Autodesk Fusion 360 part; units mm, degrees
(part 5 of 28)
  line L2664 (86.6129, 73.4851, -1.4859) -> (86.6129, 65.3433, -1.4859)
  line L2665 (86.6129, 65.3433, -1.4859) -> (86.7412, 65.3016, -1.4859)
  line L2666 (86.7412, 65.3016, -1.4859) -> (86.916, 65.2126, -1.4859)
  line L2667 (86.916, 65.2126, -1.4859) -> (87.0747, 65.0973, -1.4859)
  line L2668 (87.0747, 65.0973, -1.4859) -> (87.2134, 64.9586, -1.4859)
  line L2669 (87.2134, 64.9586, -1.4859) -> (87.3287, 64.7999, -1.4859)
  line L2670 (87.3287, 64.7999, -1.4859) -> (87.4177, 64.6251, -1.4859)
  line L2671 (87.4177, 64.6251, -1.4859) -> (87.4784, 64.4386, -1.4859)
  line L2672 (87.4784, 64.4386, -1.4859) -> (87.509, 64.2448, -1.4859)
  line L2673 (87.509, 64.2448, -1.4859) -> (87.509, 64.0487, -1.4859)
  line L2674 (87.509, 64.0487, -1.4859) -> (87.4784, 63.855, -1.4859)
  line L2675 (87.4784, 63.855, -1.4859) -> (87.4177, 63.6684, -1.4859)
  line L2676 (87.4177, 63.6684, -1.4859) -> (87.3287, 63.4936, -1.4859)
  line L2677 (87.3287, 63.4936, -1.4859) -> (87.2134, 63.335, -1.4859)
  line L2678 (87.2134, 63.335, -1.4859) -> (87.0747, 63.1963, -1.4859)
  line L2679 (87.0747, 63.1963, -1.4859) -> (86.916, 63.081, -1.4859)
  line L2680 (86.916, 63.081, -1.4859) -> (86.7412, 62.9919, -1.4859)
  line L2681 (86.7412, 62.9919, -1.4859) -> (86.5547, 62.9313, -1.4859)
  line L2682 (86.5797, 62.9563) -> (86.5797, 62.9563)
  line L2683 (86.5547, 62.9313, -1.4859) -> (86.5547, 55.068, -1.4859)
  line L2684 (86.5547, 55.068, -1.4859) -> (86.5947, 55.0476, -1.4859)
  line L2685 (86.5947, 55.0476, -1.4859) -> (86.7503, 54.9346, -1.4859)
  line L2686 (86.7503, 54.9346, -1.4859) -> (86.8862, 54.7987, -1.4859)
  line L2687 (86.8862, 54.7987, -1.4859) -> (86.9992, 54.6432, -1.4859)
  line L2688 (86.9992, 54.6432, -1.4859) -> (87.0864, 54.4719, -1.4859)
  line L2689 (87.0864, 54.4719, -1.4859) -> (87.1458, 54.2891, -1.4859)
  line L2690 (87.1458, 54.2891, -1.4859) -> (87.1759, 54.0992, -1.4859)
  line L2691 (87.1759, 54.0992, -1.4859) -> (87.1797, 54.0031, -1.4859)
  line L2692 (87.1797, 54.0031, -1.4859) -> (87.1797, 53.4531, -1.4859)
  line L2693 (87.1797, 53.4531, -1.4859) -> (87.1759, 53.357, -1.4859)
  line L2694 (87.1759, 53.357, -1.4859) -> (87.1458, 53.1671, -1.4859)
  line L2695 (87.1458, 53.1671, -1.4859) -> (87.0864, 52.9843, -1.4859)
  line L2696 (87.0864, 52.9843, -1.4859) -> (86.9992, 52.8131, -1.4859)
  line L2697 (86.9992, 52.8131, -1.4859) -> (86.8862, 52.6575, -1.4859)
  line L2698 (86.8862, 52.6575, -1.4859) -> (86.7503, 52.5216, -1.4859)
  line L2699 (86.7503, 52.5216, -1.4859) -> (86.5947, 52.4086, -1.4859)
  line L2700 (86.5947, 52.4086, -1.4859) -> (86.4235, 52.3214, -1.4859)
  line L2701 (86.4235, 52.3214, -1.4859) -> (86.2407, 52.262, -1.4859)
  line L2702 (86.2407, 52.262, -1.4859) -> (86.0508, 52.2319, -1.4859)
  line L2703 (86.0508, 52.2319, -1.4859) -> (85.8586, 52.2319, -1.4859)
  line L2704 (85.8586, 52.2319, -1.4859) -> (85.6687, 52.262, -1.4859)
  line L2705 (85.6687, 52.262, -1.4859) -> (85.4859, 52.3214, -1.4859)
  line L2706 (85.4859, 52.3214, -1.4859) -> (85.3146, 52.4086, -1.4859)
  line L2707 (85.3146, 52.4086, -1.4859) -> (85.1591, 52.5216, -1.4859)
  line L2708 (85.1591, 52.5216, -1.4859) -> (85.0232, 52.6575, -1.4859)
  line L2709 (85.0232, 52.6575, -1.4859) -> (84.9102, 52.8131, -1.4859)
  line L2710 (84.9102, 52.8131, -1.4859) -> (84.8229, 52.9843, -1.4859)
  line L2711 (84.8229, 52.9843, -1.4859) -> (84.7635, 53.1671, -1.4859)
  line L2712 (84.7635, 53.1671, -1.4859) -> (84.7335, 53.357, -1.4859)
  line L2713 (84.7335, 53.357, -1.4859) -> (84.7297, 53.4531, -1.4859)
  line L2714 (84.7297, 53.4531, -1.4859) -> (84.7297, 54.0031, -1.4859)
  line L2715 (84.7297, 54.0031, -1.4859) -> (84.7335, 54.0992, -1.4859)
  line L2716 (84.7335, 54.0992, -1.4859) -> (84.7635, 54.2891, -1.4859)
  line L2717 (84.7635, 54.2891, -1.4859) -> (84.8229, 54.4719, -1.4859)
  line L2718 (84.8229, 54.4719, -1.4859) -> (84.9102, 54.6432, -1.4859)
  line L2719 (84.9102, 54.6432, -1.4859) -> (85.0232, 54.7987, -1.4859)
  line L2720 (85.0232, 54.7987, -1.4859) -> (85.1591, 54.9346, -1.4859)
  line L2721 (85.1591, 54.9346, -1.4859) -> (85.3146, 55.0476, -1.4859)
  line L2722 (85.3146, 55.0476, -1.4859) -> (85.3547, 55.068, -1.4859)
  line L2723 (85.3547, 55.068, -1.4859) -> (85.3547, 62.9691, -1.4859)
  line L2724 (85.3547, 62.9691, -1.4859) -> (85.2845, 62.9919, -1.4859)
  line L2725 (85.2845, 62.9919, -1.4859) -> (85.1098, 63.081, -1.4859)
  line L2726 (85.1098, 63.081, -1.4859) -> (84.9511, 63.1963, -1.4859)
  line L2727 (84.9511, 63.1963, -1.4859) -> (84.8124, 63.335, -1.4859)
  line L2728 (84.8124, 63.335, -1.4859) -> (84.6971, 63.4936, -1.4859)
  line L2729 (84.6971, 63.4936, -1.4859) -> (84.608, 63.6684, -1.4859)
  line L2730 (84.608, 63.6684, -1.4859) -> (84.5474, 63.855, -1.4859)
  line L2731 (84.5474, 63.855, -1.4859) -> (84.5167, 64.0487, -1.4859)
  line L2732 (84.5167, 64.0487, -1.4859) -> (84.5167, 64.2448, -1.4859)
  line L2733 (84.5167, 64.2448, -1.4859) -> (84.5474, 64.4386, -1.4859)
  line L2734 (84.5474, 64.4386, -1.4859) -> (84.608, 64.6251, -1.4859)
  line L2735 (84.608, 64.6251, -1.4859) -> (84.6971, 64.7999, -1.4859)
  line L2736 (84.6971, 64.7999, -1.4859) -> (84.8124, 64.9586, -1.4859)
  line L2737 (84.8124, 64.9586, -1.4859) -> (84.9511, 65.0973, -1.4859)
  line L2738 (84.9511, 65.0973, -1.4859) -> (85.1098, 65.2126, -1.4859)
  line L2739 (85.1098, 65.2126, -1.4859) -> (85.2845, 65.3016, -1.4859)
  line L2740 (85.2845, 65.3016, -1.4859) -> (85.4129, 65.3433, -1.4859)
  line L2741 (85.4129, 65.3433, -1.4859) -> (85.4129, 73.4699, -1.4859)
  line L2742 (85.4129, 73.4699, -1.4859) -> (85.3671, 73.5005, -1.4859)
  line L2743 (85.3671, 73.5005, -1.4859) -> (85.2285, 73.6391, -1.4859)
  line L2744 (85.2285, 73.6391, -1.4859) -> (85.1196, 73.8021, -1.4859)
  line L2745 (85.1196, 73.8021, -1.4859) -> (85.0446, 73.9832, -1.4859)
  line L2746 (85.0446, 73.9832, -1.4859) -> (85.0063, 74.1755, -1.4859)
  line L2747 (85.0063, 74.1755, -1.4859) -> (85.0015, 74.2735, -1.4859)
  line L2748 (85.0015, 74.2735, -1.4859) -> (85.0015, 75.4735, -1.4859)
  line L2749 (85.0015, 75.4735, -1.4859) -> (85.0063, 75.5715, -1.4859)
  line L2750 (85.0063, 75.5715, -1.4859) -> (85.0446, 75.7638, -1.4859)
  line L2751 (85.0446, 75.7638, -1.4859) -> (85.1196, 75.9449, -1.4859)
  line L2752 (85.1196, 75.9449, -1.4859) -> (85.2285, 76.1079, -1.4859)
  line L2753 (85.2285, 76.1079, -1.4859) -> (85.3671, 76.2465, -1.4859)
  line L2754 (85.3671, 76.2465, -1.4859) -> (85.5301, 76.3554, -1.4859)
  line L2755 (85.5301, 76.3554, -1.4859) -> (85.7112, 76.4304, -1.4859)
  line L2756 (85.7112, 76.4304, -1.4859) -> (85.9035, 76.4687, -1.4859)
  line L2757 (85.9035, 76.4687, -1.4859) -> (86.0995, 76.4687, -1.4859)
  line L2758 (86.0995, 76.4687, -1.4859) -> (86.2918, 76.4304, -1.4859)
  line L2759 (121.2168, 76.4304, -1.4859) -> (121.3979, 76.3554, -1.4859)
  line L2760 (121.3979, 76.3554, -1.4859) -> (121.5609, 76.2465, -1.4859)
  line L2761 (121.5609, 76.2465, -1.4859) -> (121.6995, 76.1079, -1.4859)
  line L2762 (121.6995, 76.1079, -1.4859) -> (121.8084, 75.9449, -1.4859)
  line L2763 (121.8084, 75.9449, -1.4859) -> (121.8835, 75.7638, -1.4859)
  line L2764 (121.8835, 75.7638, -1.4859) -> (121.9217, 75.5715, -1.4859)
  line L2765 (121.9217, 75.5715, -1.4859) -> (121.9265, 75.4735, -1.4859)
  line L2766 (121.9265, 75.4735, -1.4859) -> (121.9265, 74.2735, -1.4859)
  line L2767 (121.9265, 74.2735, -1.4859) -> (121.9217, 74.1755, -1.4859)
  line L2768 (121.9217, 74.1755, -1.4859) -> (121.8835, 73.9832, -1.4859)
  line L2769 (121.8835, 73.9832, -1.4859) -> (121.8084, 73.8021, -1.4859)
  line L2770 (121.8084, 73.8021, -1.4859) -> (121.6995, 73.6391, -1.4859)
  line L2771 (121.6995, 73.6391, -1.4859) -> (121.5609, 73.5005, -1.4859)
  line L2772 (121.5609, 73.5005, -1.4859) -> (121.5379, 73.4851, -1.4859)
  line L2773 (121.5379, 73.4851, -1.4859) -> (121.5379, 65.3433, -1.4859)
  line L2774 (121.5379, 65.3433, -1.4859) -> (121.6662, 65.3016, -1.4859)
  line L2775 (121.6662, 65.3016, -1.4859) -> (121.841, 65.2126, -1.4859)
  line L2776 (121.841, 65.2126, -1.4859) -> (121.9997, 65.0973, -1.4859)
  line L2777 (121.9997, 65.0973, -1.4859) -> (122.1384, 64.9586, -1.4859)
  line L2778 (122.1384, 64.9586, -1.4859) -> (122.2537, 64.7999, -1.4859)
  line L2779 (122.2537, 64.7999, -1.4859) -> (122.3427, 64.6251, -1.4859)
  line L2780 (122.3427, 64.6251, -1.4859) -> (122.4033, 64.4386, -1.4859)
  line L2781 (122.4033, 64.4386, -1.4859) -> (122.434, 64.2448, -1.4859)
  line L2782 (122.434, 64.2448, -1.4859) -> (122.434, 64.0487, -1.4859)
  line L2783 (122.434, 64.0487, -1.4859) -> (122.4033, 63.855, -1.4859)
  line L2784 (122.4034, 63.855, -1.4859) -> (122.3427, 63.6684, -1.4859)
  line L2785 (122.3427, 63.6684, -1.4859) -> (122.2537, 63.4936, -1.4859)
  line L2786 (122.2537, 63.4936, -1.4859) -> (122.1384, 63.335, -1.4859)
  line L2787 (122.1384, 63.335, -1.4859) -> (121.9997, 63.1963, -1.4859)
  line L2788 (121.9997, 63.1963, -1.4859) -> (121.841, 63.081, -1.4859)
  line L2789 (121.841, 63.081, -1.4859) -> (121.6662, 62.9919, -1.4859)
  line L2790 (121.6662, 62.9919, -1.4859) -> (121.4797, 62.9313, -1.4859)
  line L2791 (121.5047, 62.9563) -> (121.5047, 62.9563)
  line L2792 (121.4797, 62.9313, -1.4859) -> (121.4797, 55.068, -1.4859)
  line L2793 (121.4797, 55.068, -1.4859) -> (121.5197, 55.0476, -1.4859)
  line L2794 (121.5197, 55.0476, -1.4859) -> (121.6753, 54.9346, -1.4859)
  line L2795 (121.6753, 54.9346, -1.4859) -> (121.8112, 54.7987, -1.4859)
  line L2796 (121.8112, 54.7987, -1.4859) -> (121.9242, 54.6432, -1.4859)
  line L2797 (121.9242, 54.6432, -1.4859) -> (122.0114, 54.4719, -1.4859)
  line L2798 (122.0114, 54.4719, -1.4859) -> (122.0708, 54.2891, -1.4859)
  line L2799 (122.0708, 54.2891, -1.4859) -> (122.1009, 54.0992, -1.4859)
  line L2800 (122.1009, 54.0992, -1.4859) -> (122.1047, 54.0031, -1.4859)
  line L2801 (122.1047, 54.0031, -1.4859) -> (122.1047, 53.4531, -1.4859)
  line L2802 (122.1047, 53.4531, -1.4859) -> (122.1009, 53.357, -1.4859)
  line L2803 (122.1009, 53.357, -1.4859) -> (122.0708, 53.1671, -1.4859)
  line L2804 (122.0708, 53.1671, -1.4859) -> (122.0114, 52.9843, -1.4859)
  line L2805 (122.0114, 52.9843, -1.4859) -> (121.9242, 52.8131, -1.4859)
  line L2806 (121.9242, 52.8131, -1.4859) -> (121.8112, 52.6575, -1.4859)
  line L2807 (121.8112, 52.6575, -1.4859) -> (121.6753, 52.5216, -1.4859)
  line L2808 (121.6753, 52.5216, -1.4859) -> (121.5197, 52.4086, -1.4859)
  line L2809 (121.5197, 52.4086, -1.4859) -> (121.3485, 52.3214, -1.4859)
  line L2810 (121.3485, 52.3214, -1.4859) -> (121.1657, 52.262, -1.4859)
  line L2811 (121.1657, 52.262, -1.4859) -> (120.9758, 52.2319, -1.4859)
  line L2812 (120.9758, 52.2319, -1.4859) -> (120.7836, 52.2319, -1.4859)
  line L2813 (120.7836, 52.2319, -1.4859) -> (120.5937, 52.262, -1.4859)
  line L2814 (120.5937, 52.262, -1.4859) -> (120.4109, 52.3214, -1.4859)
  line L2815 (120.4109, 52.3214, -1.4859) -> (120.2396, 52.4086, -1.4859)
  line L2816 (120.2396, 52.4086, -1.4859) -> (120.0841, 52.5216, -1.4859)
  line L2817 (120.0841, 52.5216, -1.4859) -> (119.9482, 52.6575, -1.4859)
  line L2818 (119.9482, 52.6575, -1.4859) -> (119.8352, 52.8131, -1.4859)
  line L2819 (119.8352, 52.8131, -1.4859) -> (119.7479, 52.9843, -1.4859)
  line L2820 (119.7479, 52.9843, -1.4859) -> (119.6885, 53.1671, -1.4859)
  line L2821 (119.6885, 53.1671, -1.4859) -> (119.6585, 53.357, -1.4859)
  line L2822 (119.6585, 53.357, -1.4859) -> (119.6547, 53.4531, -1.4859)
  line L2823 (119.6547, 53.4531, -1.4859) -> (119.6547, 54.0031, -1.4859)
  line L2824 (119.6547, 54.0031, -1.4859) -> (119.6585, 54.0992, -1.4859)
  line L2825 (119.6585, 54.0992, -1.4859) -> (119.6885, 54.2891, -1.4859)
  line L2826 (119.6885, 54.2891, -1.4859) -> (119.7479, 54.4719, -1.4859)
  line L2827 (119.7479, 54.4719, -1.4859) -> (119.8352, 54.6432, -1.4859)
  line L2828 (119.8352, 54.6432, -1.4859) -> (119.9482, 54.7987, -1.4859)
  line L2829 (119.9482, 54.7987, -1.4859) -> (120.0841, 54.9346, -1.4859)
  line L2830 (120.0841, 54.9346, -1.4859) -> (120.2396, 55.0476, -1.4859)
  line L2831 (120.2396, 55.0476, -1.4859) -> (120.2797, 55.068, -1.4859)
  line L2832 (120.2797, 55.068, -1.4859) -> (120.2797, 62.9691, -1.4859)
  line L2833 (120.2797, 62.9691, -1.4859) -> (120.2095, 62.9919, -1.4859)
  line L2834 (120.2095, 62.9919, -1.4859) -> (120.0348, 63.081, -1.4859)
  line L2835 (120.0348, 63.081, -1.4859) -> (119.8761, 63.1963, -1.4859)
  line L2836 (119.8761, 63.1963, -1.4859) -> (119.7374, 63.335, -1.4859)
  line L2837 (119.7374, 63.335, -1.4859) -> (119.6221, 63.4936, -1.4859)
  line L2838 (119.6221, 63.4936, -1.4859) -> (119.533, 63.6684, -1.4859)
  line L2839 (119.533, 63.6684, -1.4859) -> (119.4724, 63.855, -1.4859)
  line L2840 (119.4724, 63.855, -1.4859) -> (119.4417, 64.0487, -1.4859)
  line L2841 (119.4417, 64.0487, -1.4859) -> (119.4417, 64.2448, -1.4859)
  line L2842 (119.4417, 64.2448, -1.4859) -> (119.4724, 64.4386, -1.4859)
  line L2843 (119.4724, 64.4386, -1.4859) -> (119.533, 64.6251, -1.4859)
  line L2844 (119.533, 64.6251, -1.4859) -> (119.6221, 64.7999, -1.4859)
  line L2845 (119.6221, 64.7999, -1.4859) -> (119.7374, 64.9586, -1.4859)
  line L2846 (119.7374, 64.9586, -1.4859) -> (119.8761, 65.0973, -1.4859)
  line L2847 (119.8761, 65.0973, -1.4859) -> (120.0348, 65.2126, -1.4859)
  line L2848 (120.0348, 65.2126, -1.4859) -> (120.2095, 65.3016, -1.4859)
  line L2849 (120.2095, 65.3016, -1.4859) -> (120.3379, 65.3433, -1.4859)
  line L2850 (120.3379, 65.3433, -1.4859) -> (120.3379, 73.4699, -1.4859)
  line L2851 (120.3379, 73.4699, -1.4859) -> (120.2921, 73.5005, -1.4859)
  line L2852 (120.2921, 73.5005, -1.4859) -> (120.1535, 73.6391, -1.4859)
  line L2853 (120.1535, 73.6391, -1.4859) -> (120.0446, 73.8021, -1.4859)
  line L2854 (120.0446, 73.8021, -1.4859) -> (119.9696, 73.9832, -1.4859)
  line L2855 (119.9696, 73.9832, -1.4859) -> (119.9313, 74.1755, -1.4859)
  line L2856 (119.9313, 74.1755, -1.4859) -> (119.9265, 74.2735, -1.4859)
  line L2857 (119.9265, 74.2735, -1.4859) -> (119.9265, 75.4735, -1.4859)
  line L2858 (119.9265, 75.4735, -1.4859) -> (119.9313, 75.5715, -1.4859)
  line L2859 (119.9313, 75.5715, -1.4859) -> (119.9696, 75.7638, -1.4859)
  line L2860 (119.9696, 75.7638, -1.4859) -> (120.0446, 75.9449, -1.4859)
  line L2861 (120.0446, 75.9449, -1.4859) -> (120.1535, 76.1079, -1.4859)
  line L2862 (120.1535, 76.1079, -1.4859) -> (120.2921, 76.2465, -1.4859)
  line L2863 (120.2921, 76.2465, -1.4859) -> (120.4551, 76.3554, -1.4859)
  line L2864 (120.4551, 76.3554, -1.4859) -> (120.6362, 76.4304, -1.4859)
  line L2865 (120.6362, 76.4304, -1.4859) -> (120.8285, 76.4687, -1.4859)
  line L2866 (120.8285, 76.4687, -1.4859) -> (121.0245, 76.4687, -1.4859)
  line L2867 (121.0245, 76.4687, -1.4859) -> (121.2168, 76.4304, -1.4859)
  line L2868 (32.9849, 62.5322, -1.4859) -> (33.1714, 62.4716, -1.4859)
  line L2869 (33.1714, 62.4716, -1.4859) -> (33.3462, 62.3825, -1.4859)
  line L2870 (33.3462, 62.3825, -1.4859) -> (33.5049, 62.2672, -1.4859)
  line L2871 (33.5049, 62.2672, -1.4859) -> (33.6436, 62.1286, -1.4859)
  line L2872 (33.6436, 62.1286, -1.4859) -> (33.7588, 61.9699, -1.4859)
  line L2873 (33.7588, 61.9699, -1.4859) -> (33.8479, 61.7951, -1.4859)
  line L2874 (33.8479, 61.7951, -1.4859) -> (33.9085, 61.6085, -1.4859)
  line L2875 (33.9085, 61.6085, -1.4859) -> (33.9392, 61.4148, -1.4859)
  line L2876 (33.9392, 61.4148, -1.4859) -> (33.943, 61.3167, -1.4859)
  line L2877 (33.943, 61.3167, -1.4859) -> (33.943, 60.8167, -1.4859)
  line L2878 (33.943, 60.8167, -1.4859) -> (33.9392, 60.7187, -1.4859)
  line L2879 (33.9392, 60.7187, -1.4859) -> (33.9085, 60.5249, -1.4859)
  line L2880 (33.9085, 60.5249, -1.4859) -> (33.8479, 60.3384, -1.4859)
  line L2881 (33.8479, 60.3384, -1.4859) -> (33.7588, 60.1636, -1.4859)
  line L2882 (33.7588, 60.1636, -1.4859) -> (33.6436, 60.0049, -1.4859)
  line L2883 (33.6436, 60.0049, -1.4859) -> (33.5049, 59.8662, -1.4859)
  line L2884 (33.5049, 59.8662, -1.4859) -> (33.3462, 59.7509, -1.4859)
  line L2885 (33.3462, 59.7509, -1.4859) -> (33.1714, 59.6619, -1.4859)
  line L2886 (33.1714, 59.6619, -1.4859) -> (32.9848, 59.6013, -1.4859)
  line L2887 (32.9848, 59.6013, -1.4859) -> (32.7911, 59.5706, -1.4859)
  line L2888 (32.7911, 59.5706, -1.4859) -> (32.595, 59.5706, -1.4859)
  line L2889 (32.595, 59.5706, -1.4859) -> (32.4012, 59.6013, -1.4859)
  line L2890 (32.4012, 59.6013, -1.4859) -> (32.2147, 59.6619, -1.4859)
  line L2891 (32.2147, 59.6619, -1.4859) -> (32.0399, 59.7509, -1.4859)
  line L2892 (32.0399, 59.7509, -1.4859) -> (31.8812, 59.8662, -1.4859)
  line L2893 (31.8812, 59.8662, -1.4859) -> (31.7425, 60.0049, -1.4859)
  line L2894 (31.7425, 60.0049, -1.4859) -> (31.6272, 60.1636, -1.4859)
  line L2895 (31.6272, 60.1636, -1.4859) -> (31.5382, 60.3384, -1.4859)
  line L2896 (31.5382, 60.3384, -1.4859) -> (31.4776, 60.5249, -1.4859)
  line L2897 (31.4776, 60.5249, -1.4859) -> (31.4469, 60.7187, -1.4859)
  line L2898 (31.4469, 60.7187, -1.4859) -> (31.443, 60.8167, -1.4859)
  line L2899 (31.443, 60.8167, -1.4859) -> (31.443, 61.3167, -1.4859)
  line L2900 (31.443, 61.3167, -1.4859) -> (31.4469, 61.4148, -1.4859)
  line L2901 (31.4469, 61.4148, -1.4859) -> (31.4776, 61.6085, -1.4859)
  line L2902 (31.4776, 61.6085, -1.4859) -> (31.5382, 61.7951, -1.4859)
  line L2903 (31.5382, 61.7951, -1.4859) -> (31.6272, 61.9699, -1.4859)
  line L2904 (31.6272, 61.9699, -1.4859) -> (31.7425, 62.1286, -1.4859)
  line L2905 (31.7425, 62.1286, -1.4859) -> (31.8812, 62.2672, -1.4859)
  line L2906 (31.8812, 62.2672, -1.4859) -> (32.0399, 62.3825, -1.4859)
  line L2907 (32.0399, 62.3825, -1.4859) -> (32.2147, 62.4716, -1.4859)
  line L2908 (32.2147, 62.4716, -1.4859) -> (32.4012, 62.5322, -1.4859)
  line L2909 (32.4012, 62.5322, -1.4859) -> (32.595, 62.5629, -1.4859)
  line L2910 (32.595, 62.5629, -1.4859) -> (32.7911, 62.5629, -1.4859)
  line L2911 (32.7911, 62.5629, -1.4859) -> (32.9848, 62.5322, -1.4859)
  line L2912 (67.9098, 62.5322, -1.4859) -> (68.0964, 62.4716, -1.4859)
  line L2913 (68.0964, 62.4716, -1.4859) -> (68.2712, 62.3825, -1.4859)
  line L2914 (68.2712, 62.3825, -1.4859) -> (68.4299, 62.2672, -1.4859)
  line L2915 (68.4299, 62.2672, -1.4859) -> (68.5686, 62.1286, -1.4859)
  line L2916 (68.5685, 62.1286, -1.4859) -> (68.6838, 61.9699, -1.4859)
  line L2917 (68.6838, 61.9699, -1.4859) -> (68.7729, 61.7951, -1.4859)
  line L2918 (68.7729, 61.7951, -1.4859) -> (68.8335, 61.6085, -1.4859)
  line L2919 (68.8335, 61.6085, -1.4859) -> (68.8642, 61.4148, -1.4859)
  line L2920 (68.8642, 61.4148, -1.4859) -> (68.868, 61.3167, -1.4859)
  line L2921 (68.868, 61.3167, -1.4859) -> (68.868, 60.8167, -1.4859)
  line L2922 (68.868, 60.8167, -1.4859) -> (68.8642, 60.7187, -1.4859)
  line L2923 (68.8642, 60.7187, -1.4859) -> (68.8335, 60.5249, -1.4859)
  line L2924 (68.8335, 60.5249, -1.4859) -> (68.7729, 60.3384, -1.4859)
  line L2925 (68.7729, 60.3384, -1.4859) -> (68.6838, 60.1636, -1.4859)
  line L2926 (68.6838, 60.1636, -1.4859) -> (68.5686, 60.0049, -1.4859)
  line L2927 (68.5685, 60.0049, -1.4859) -> (68.4299, 59.8662, -1.4859)
  line L2928 (68.4299, 59.8662, -1.4859) -> (68.2712, 59.7509, -1.4859)
  line L2929 (68.2712, 59.7509, -1.4859) -> (68.0964, 59.6619, -1.4859)
  line L2930 (68.0964, 59.6619, -1.4859) -> (67.9099, 59.6013, -1.4859)
  line L2931 (67.9098, 59.6013, -1.4859) -> (67.7161, 59.5706, -1.4859)
  line L2932 (67.7161, 59.5706, -1.4859) -> (67.52, 59.5706, -1.4859)
  line L2933 (67.52, 59.5706, -1.4859) -> (67.3262, 59.6013, -1.4859)
  line L2934 (67.3262, 59.6013, -1.4859) -> (67.1397, 59.6619, -1.4859)
  line L2935 (67.1397, 59.6619, -1.4859) -> (66.9649, 59.7509, -1.4859)
  line L2936 (66.9649, 59.7509, -1.4859) -> (66.8062, 59.8662, -1.4859)
  line L2937 (66.8062, 59.8662, -1.4859) -> (66.6675, 60.0049, -1.4859)
  line L2938 (66.6675, 60.0049, -1.4859) -> (66.5522, 60.1636, -1.4859)
  line L2939 (66.5522, 60.1636, -1.4859) -> (66.4632, 60.3384, -1.4859)
  line L2940 (66.4632, 60.3384, -1.4859) -> (66.4026, 60.5249, -1.4859)
  line L2941 (66.4026, 60.5249, -1.4859) -> (66.3719, 60.7187, -1.4859)
  line L2942 (66.3719, 60.7187, -1.4859) -> (66.368, 60.8167, -1.4859)
  line L2943 (66.368, 60.8167, -1.4859) -> (66.368, 61.3167, -1.4859)
  line L2944 (66.368, 61.3167, -1.4859) -> (66.3719, 61.4148, -1.4859)
  line L2945 (66.3719, 61.4148, -1.4859) -> (66.4026, 61.6085, -1.4859)
  line L2946 (66.4026, 61.6085, -1.4859) -> (66.4632, 61.7951, -1.4859)
  line L2947 (66.4632, 61.7951, -1.4859) -> (66.5522, 61.9699, -1.4859)
  line L2948 (66.5522, 61.9699, -1.4859) -> (66.6675, 62.1286, -1.4859)
  line L2949 (66.6675, 62.1286, -1.4859) -> (66.8062, 62.2672, -1.4859)
  line L2950 (66.8062, 62.2672, -1.4859) -> (66.9649, 62.3825, -1.4859)
  line L2951 (66.9649, 62.3825, -1.4859) -> (67.1397, 62.4716, -1.4859)
  line L2952 (67.1397, 62.4716, -1.4859) -> (67.3262, 62.5322, -1.4859)
  line L2953 (67.3262, 62.5322, -1.4859) -> (67.52, 62.5629, -1.4859)
  line L2954 (67.52, 62.5629, -1.4859) -> (67.7161, 62.5629, -1.4859)
  line L2955 (67.7161, 62.5629, -1.4859) -> (67.9098, 62.5322, -1.4859)
  line L2956 (102.8349, 62.5322, -1.4859) -> (103.0214, 62.4716, -1.4859)
  line L2957 (103.0214, 62.4716, -1.4859) -> (103.1962, 62.3825, -1.4859)
  line L2958 (103.1962, 62.3825, -1.4859) -> (103.3549, 62.2672, -1.4859)
  line L2959 (103.3549, 62.2672, -1.4859) -> (103.4936, 62.1286, -1.4859)
  line L2960 (103.4936, 62.1286, -1.4859) -> (103.6088, 61.9699, -1.4859)
  line L2961 (103.6088, 61.9699, -1.4859) -> (103.6979, 61.7951, -1.4859)
  line L2962 (103.6979, 61.7951, -1.4859) -> (103.7585, 61.6085, -1.4859)
  line L2963 (103.7585, 61.6085, -1.4859) -> (103.7892, 61.4148, -1.4859)
  line L2964 (103.7892, 61.4148, -1.4859) -> (103.793, 61.3167, -1.4859)
  line L2965 (103.793, 61.3167, -1.4859) -> (103.793, 60.8167, -1.4859)
  line L2966 (103.793, 60.8167, -1.4859) -> (103.7892, 60.7187, -1.4859)
  line L2967 (103.7892, 60.7187, -1.4859) -> (103.7585, 60.5249, -1.4859)
  line L2968 (103.7585, 60.5249, -1.4859) -> (103.6979, 60.3384, -1.4859)
  line L2969 (103.6979, 60.3384, -1.4859) -> (103.6088, 60.1636, -1.4859)
  line L2970 (103.6088, 60.1636, -1.4859) -> (103.4936, 60.0049, -1.4859)
  line L2971 (103.4936, 60.0049, -1.4859) -> (103.3549, 59.8662, -1.4859)
  line L2972 (103.3549, 59.8662, -1.4859) -> (103.1962, 59.7509, -1.4859)
  line L2973 (103.1962, 59.7509, -1.4859) -> (103.0214, 59.6619, -1.4859)
  line L2974 (103.0214, 59.6619, -1.4859) -> (102.8349, 59.6013, -1.4859)
  line L2975 (102.8349, 59.6013, -1.4859) -> (102.6411, 59.5706, -1.4859)
  line L2976 (102.6411, 59.5706, -1.4859) -> (102.445, 59.5706, -1.4859)
  line L2977 (102.445, 59.5706, -1.4859) -> (102.2512, 59.6013, -1.4859)
  line L2978 (102.2512, 59.6013, -1.4859) -> (102.0647, 59.6619, -1.4859)
  line L2979 (102.0647, 59.6619, -1.4859) -> (101.8899, 59.7509, -1.4859)
  line L2980 (101.8899, 59.7509, -1.4859) -> (101.7312, 59.8662, -1.4859)
  line L2981 (101.7312, 59.8662, -1.4859) -> (101.5925, 60.0049, -1.4859)
  line L2982 (101.5925, 60.0049, -1.4859) -> (101.4772, 60.1636, -1.4859)
  line L2983 (101.4772, 60.1636, -1.4859) -> (101.3882, 60.3384, -1.4859)
  line L2984 (101.3882, 60.3384, -1.4859) -> (101.3276, 60.5249, -1.4859)
  line L2985 (101.3276, 60.5249, -1.4859) -> (101.2969, 60.7187, -1.4859)
  line L2986 (101.2969, 60.7187, -1.4859) -> (101.293, 60.8167, -1.4859)
  line L2987 (101.293, 60.8167, -1.4859) -> (101.293, 61.3167, -1.4859)
  line L2988 (101.293, 61.3167, -1.4859) -> (101.2969, 61.4148, -1.4859)
  line L2989 (101.2969, 61.4148, -1.4859) -> (101.3276, 61.6085, -1.4859)
  line L2990 (101.3276, 61.6085, -1.4859) -> (101.3882, 61.7951, -1.4859)
  line L2991 (101.3882, 61.7951, -1.4859) -> (101.4772, 61.9699, -1.4859)
  line L2992 (101.4772, 61.9699, -1.4859) -> (101.5925, 62.1286, -1.4859)
  line L2993 (101.5925, 62.1286, -1.4859) -> (101.7312, 62.2672, -1.4859)
  line L2994 (101.7312, 62.2672, -1.4859) -> (101.8899, 62.3825, -1.4859)
  line L2995 (101.8899, 62.3825, -1.4859) -> (102.0647, 62.4716, -1.4859)
  line L2996 (102.0647, 62.4716, -1.4859) -> (102.2512, 62.5322, -1.4859)
  line L2997 (102.2512, 62.5322, -1.4859) -> (102.445, 62.5629, -1.4859)
  line L2998 (102.445, 62.5629, -1.4859) -> (102.6411, 62.5629, -1.4859)
  line L2999 (102.6411, 62.5629, -1.4859) -> (102.8349, 62.5322, -1.4859)
  line L3000 (137.7599, 62.5322, -1.4859) -> (137.9464, 62.4716, -1.4859)
  line L3001 (137.9464, 62.4716, -1.4859) -> (138.1212, 62.3825, -1.4859)
  line L3002 (138.1212, 62.3825, -1.4859) -> (138.2799, 62.2672, -1.4859)
  line L3003 (138.2799, 62.2672, -1.4859) -> (138.4186, 62.1286, -1.4859)
  line L3004 (138.4186, 62.1286, -1.4859) -> (138.5338, 61.9699, -1.4859)
  line L3005 (138.5338, 61.9699, -1.4859) -> (138.6229, 61.7951, -1.4859)
  line L3006 (138.6229, 61.7951, -1.4859) -> (138.6835, 61.6085, -1.4859)
  line L3007 (138.6835, 61.6085, -1.4859) -> (138.7142, 61.4148, -1.4859)
  line L3008 (138.7142, 61.4148, -1.4859) -> (138.718, 61.3167, -1.4859)
  line L3009 (138.718, 61.3167, -1.4859) -> (138.718, 60.8167, -1.4859)
  line L3010 (138.718, 60.8167, -1.4859) -> (138.7142, 60.7187, -1.4859)
  line L3011 (138.7142, 60.7187, -1.4859) -> (138.6835, 60.5249, -1.4859)
  line L3012 (138.6835, 60.5249, -1.4859) -> (138.6229, 60.3384, -1.4859)
  line L3013 (138.6229, 60.3384, -1.4859) -> (138.5338, 60.1636, -1.4859)
  line L3014 (138.5338, 60.1636, -1.4859) -> (138.4186, 60.0049, -1.4859)
  line L3015 (138.4186, 60.0049, -1.4859) -> (138.2799, 59.8662, -1.4859)
  line L3016 (138.2799, 59.8662, -1.4859) -> (138.1212, 59.7509, -1.4859)
  line L3017 (138.1212, 59.7509, -1.4859) -> (137.9464, 59.6619, -1.4859)
  line L3018 (137.9464, 59.6619, -1.4859) -> (137.7599, 59.6013, -1.4859)
  line L3019 (137.7599, 59.6013, -1.4859) -> (137.5661, 59.5706, -1.4859)
  line L3020 (137.5661, 59.5706, -1.4859) -> (137.37, 59.5706, -1.4859)
  line L3021 (137.37, 59.5706, -1.4859) -> (137.1762, 59.6013, -1.4859)
  line L3022 (137.1762, 59.6013, -1.4859) -> (136.9897, 59.6619, -1.4859)
  line L3023 (136.9897, 59.6619, -1.4859) -> (136.8149, 59.7509, -1.4859)
  line L3024 (136.8149, 59.7509, -1.4859) -> (136.6562, 59.8662, -1.4859)
  line L3025 (136.6562, 59.8662, -1.4859) -> (136.5175, 60.0049, -1.4859)
  line L3026 (136.5175, 60.0049, -1.4859) -> (136.4022, 60.1636, -1.4859)
  line L3027 (136.4022, 60.1636, -1.4859) -> (136.3132, 60.3384, -1.4859)
  line L3028 (136.3132, 60.3384, -1.4859) -> (136.2526, 60.5249, -1.4859)
  line L3029 (136.2526, 60.5249, -1.4859) -> (136.2219, 60.7187, -1.4859)
  line L3030 (136.2219, 60.7187, -1.4859) -> (136.218, 60.8167, -1.4859)
  line L3031 (136.218, 60.8167, -1.4859) -> (136.218, 61.3167, -1.4859)
  line L3032 (136.218, 61.3167, -1.4859) -> (136.2219, 61.4148, -1.4859)
  line L3033 (136.2219, 61.4148, -1.4859) -> (136.2526, 61.6085, -1.4859)
  line L3034 (136.2526, 61.6085, -1.4859) -> (136.3132, 61.7951, -1.4859)
  line L3035 (136.3132, 61.7951, -1.4859) -> (136.4022, 61.9699, -1.4859)
  line L3036 (136.4022, 61.9699, -1.4859) -> (136.5175, 62.1286, -1.4859)
  line L3037 (136.5175, 62.1286, -1.4859) -> (136.6562, 62.2672, -1.4859)
  line L3038 (136.6562, 62.2672, -1.4859) -> (136.8149, 62.3825, -1.4859)
  line L3039 (136.8149, 62.3825, -1.4859) -> (136.9897, 62.4716, -1.4859)
  line L3040 (136.9897, 62.4716, -1.4859) -> (137.1762, 62.5322, -1.4859)
  line L3041 (137.1762, 62.5322, -1.4859) -> (137.37, 62.5629, -1.4859)
  line L3042 (137.37, 62.5629, -1.4859) -> (137.5661, 62.5629, -1.4859)
  line L3043 (137.5661, 62.5629, -1.4859) -> (137.7599, 62.5322, -1.4859)
  line L3044 (24.9166, 73.2153, -1.4859) -> (22.9166, 73.2153, -1.4859)
  line L3045 (22.9166, 73.2153, -1.4859) -> (22.9166, 76.4153, -1.4859)
  line L3046 (22.9166, 76.4153, -1.4859) -> (24.9166, 76.4153, -1.4859)
  line L3047 (24.9166, 76.4153, -1.4859) -> (24.9166, 73.2153, -1.4859)
  line L3048 (59.8416, 73.2153, -1.4859) -> (57.8416, 73.2153, -1.4859)
  line L3049 (57.8416, 73.2153, -1.4859) -> (57.8416, 76.4153, -1.4859)
  line L3050 (57.8416, 76.4153, -1.4859) -> (59.8416, 76.4153, -1.4859)
  line L3051 (59.8416, 76.4153, -1.4859) -> (59.8416, 73.2153, -1.4859)
  line L3052 (94.7666, 73.2153, -1.4859) -> (92.7666, 73.2153, -1.4859)
  line L3053 (92.7666, 73.2153, -1.4859) -> (92.7666, 76.4153, -1.4859)
  line L3054 (92.7666, 76.4153, -1.4859) -> (94.7666, 76.4153, -1.4859)
  line L3055 (94.7666, 76.4153, -1.4859) -> (94.7666, 73.2153, -1.4859)
  line L3056 (129.6916, 73.2153, -1.4859) -> (127.6916, 73.2153, -1.4859)
  line L3057 (127.6916, 73.2153, -1.4859) -> (127.6916, 76.4153, -1.4859)
  line L3058 (127.6916, 76.4153, -1.4859) -> (129.6916, 76.4153, -1.4859)
  line L3059 (129.6916, 76.4153, -1.4859) -> (129.6916, 73.2153, -1.4859)
  line L3060 (26.9769, 76.3722, -1.4859) -> (27.158, 76.2972, -1.4859)
  line L3061 (27.158, 76.2972, -1.4859) -> (27.321, 76.1883, -1.4859)
  line L3062 (27.321, 76.1883, -1.4859) -> (27.4596, 76.0497, -1.4859)
  line L3063 (27.4596, 76.0497, -1.4859) -> (27.5685, 75.8867, -1.4859)
  line L3064 (27.5685, 75.8867, -1.4859) -> (27.6435, 75.7056, -1.4859)
  line L3065 (27.6435, 75.7056, -1.4859) -> (27.6818, 75.5133, -1.4859)
  line L3066 (27.6818, 75.5133, -1.4859) -> (27.6866, 75.4153, -1.4859)
  line L3067 (27.6866, 75.4153, -1.4859) -> (27.6866, 74.2153, -1.4859)
  line L3068 (27.6866, 74.2153, -1.4859) -> (27.6818, 74.1173, -1.4859)
  line L3069 (27.6818, 74.1173, -1.4859) -> (27.6435, 73.925, -1.4859)
  line L3070 (27.6435, 73.925, -1.4859) -> (27.5685, 73.7439, -1.4859)
  line L3071 (27.5685, 73.7439, -1.4859) -> (27.4596, 73.5809, -1.4859)
  line L3072 (27.4596, 73.5809, -1.4859) -> (27.321, 73.4423, -1.4859)
  line L3073 (27.321, 73.4423, -1.4859) -> (27.158, 73.3334, -1.4859)
  line L3074 (27.158, 73.3334, -1.4859) -> (26.9769, 73.2583, -1.4859)
  line L3075 (26.9769, 73.2583, -1.4859) -> (26.7846, 73.2201, -1.4859)
  line L3076 (26.7846, 73.2201, -1.4859) -> (26.5886, 73.2201, -1.4859)
  line L3077 (26.5886, 73.2201, -1.4859) -> (26.3963, 73.2583, -1.4859)
  line L3078 (26.3963, 73.2583, -1.4859) -> (26.2152, 73.3334, -1.4859)
  line L3079 (26.2152, 73.3334, -1.4859) -> (26.0522, 73.4423, -1.4859)
  line L3080 (26.0522, 73.4423, -1.4859) -> (25.9136, 73.5809, -1.4859)
  line L3081 (25.9136, 73.5809, -1.4859) -> (25.8047, 73.7439, -1.4859)
  line L3082 (25.8047, 73.7439, -1.4859) -> (25.7297, 73.925, -1.4859)
  line L3083 (25.7297, 73.925, -1.4859) -> (25.6914, 74.1173, -1.4859)
  line L3084 (25.6914, 74.1173, -1.4859) -> (25.6866, 74.2153, -1.4859)
  line L3085 (25.6866, 74.2153, -1.4859) -> (25.6866, 75.4153, -1.4859)
  line L3086 (25.6866, 75.4153, -1.4859) -> (25.6914, 75.5133, -1.4859)
  line L3087 (25.6914, 75.5133, -1.4859) -> (25.7297, 75.7056, -1.4859)
  line L3088 (25.7297, 75.7056, -1.4859) -> (25.8047, 75.8867, -1.4859)
  line L3089 (25.8047, 75.8867, -1.4859) -> (25.9136, 76.0497, -1.4859)
  line L3090 (25.9136, 76.0497, -1.4859) -> (26.0522, 76.1883, -1.4859)
  line L3091 (26.0522, 76.1883, -1.4859) -> (26.2152, 76.2972, -1.4859)
  line L3092 (26.2152, 76.2972, -1.4859) -> (26.3963, 76.3722, -1.4859)
  line L3093 (26.3963, 76.3722, -1.4859) -> (26.5886, 76.4105, -1.4859)
  line L3094 (26.5886, 76.4105, -1.4859) -> (26.7846, 76.4105, -1.4859)
  line L3095 (26.7846, 76.4105, -1.4859) -> (26.9769, 76.3722, -1.4859)
  line L3096 (29.7069, 76.3722, -1.4859) -> (29.888, 76.2972, -1.4859)
  line L3097 (29.888, 76.2972, -1.4859) -> (30.051, 76.1883, -1.4859)
  line L3098 (30.051, 76.1883, -1.4859) -> (30.1896, 76.0497, -1.4859)
  line L3099 (30.1896, 76.0497, -1.4859) -> (30.2985, 75.8867, -1.4859)
  line L3100 (30.2985, 75.8867, -1.4859) -> (30.3735, 75.7056, -1.4859)
  line L3101 (30.3735, 75.7056, -1.4859) -> (30.4118, 75.5133, -1.4859)
  line L3102 (30.4118, 75.5133, -1.4859) -> (30.4166, 75.4153, -1.4859)
  line L3103 (30.4166, 75.4153, -1.4859) -> (30.4166, 74.2153, -1.4859)
  line L3104 (30.4166, 74.2153, -1.4859) -> (30.4118, 74.1173, -1.4859)
  line L3105 (30.4118, 74.1173, -1.4859) -> (30.3735, 73.925, -1.4859)
  line L3106 (30.3735, 73.925, -1.4859) -> (30.2985, 73.7439, -1.4859)
  line L3107 (30.2985, 73.7439, -1.4859) -> (30.1896, 73.5809, -1.4859)
  line L3108 (30.1896, 73.5809, -1.4859) -> (30.051, 73.4423, -1.4859)
  line L3109 (30.051, 73.4423, -1.4859) -> (29.888, 73.3334, -1.4859)
  line L3110 (29.888, 73.3334, -1.4859) -> (29.7069, 73.2583, -1.4859)
  line L3111 (29.7069, 73.2583, -1.4859) -> (29.5146, 73.2201, -1.4859)
  line L3112 (29.5146, 73.2201, -1.4859) -> (29.3186, 73.2201, -1.4859)
  line L3113 (29.3186, 73.2201, -1.4859) -> (29.1263, 73.2583, -1.4859)
  line L3114 (29.1263, 73.2583, -1.4859) -> (28.9452, 73.3334, -1.4859)
  line L3115 (28.9452, 73.3334, -1.4859) -> (28.7822, 73.4423, -1.4859)
  line L3116 (28.7822, 73.4423, -1.4859) -> (28.6436, 73.5809, -1.4859)
  line L3117 (28.6436, 73.5809, -1.4859) -> (28.5347, 73.7439, -1.4859)
  line L3118 (28.5347, 73.7439, -1.4859) -> (28.4597, 73.925, -1.4859)
  line L3119 (28.4597, 73.925, -1.4859) -> (28.4214, 74.1173, -1.4859)
  line L3120 (28.4214, 74.1173, -1.4859) -> (28.4166, 74.2153, -1.4859)
  line L3121 (28.4166, 74.2153, -1.4859) -> (28.4166, 75.4153, -1.4859)
  line L3122 (28.4166, 75.4153, -1.4859) -> (28.4214, 75.5133, -1.4859)
  line L3123 (28.4214, 75.5133, -1.4859) -> (28.4597, 75.7056, -1.4859)
  line L3124 (28.4597, 75.7056, -1.4859) -> (28.5347, 75.8867, -1.4859)
  line L3125 (28.5347, 75.8867, -1.4859) -> (28.6436, 76.0497, -1.4859)
  line L3126 (28.6436, 76.0497, -1.4859) -> (28.7822, 76.1883, -1.4859)
  line L3127 (28.7822, 76.1883, -1.4859) -> (28.9452, 76.2972, -1.4859)
  line L3128 (28.9452, 76.2972, -1.4859) -> (29.1263, 76.3722, -1.4859)
  line L3129 (29.1263, 76.3722, -1.4859) -> (29.3186, 76.4105, -1.4859)
  line L3130 (29.3186, 76.4105, -1.4859) -> (29.5146, 76.4105, -1.4859)
  line L3131 (29.5146, 76.4105, -1.4859) -> (29.7069, 76.3722, -1.4859)
  line L3132 (61.9019, 76.3722, -1.4859) -> (62.083, 76.2972, -1.4859)
  line L3133 (62.083, 76.2972, -1.4859) -> (62.246, 76.1883, -1.4859)
  line L3134 (62.246, 76.1883, -1.4859) -> (62.3846, 76.0497, -1.4859)
  line L3135 (62.3846, 76.0497, -1.4859) -> (62.4935, 75.8867, -1.4859)
  line L3136 (62.4935, 75.8867, -1.4859) -> (62.5685, 75.7056, -1.4859)
  line L3137 (62.5685, 75.7056, -1.4859) -> (62.6068, 75.5133, -1.4859)
  line L3138 (62.6068, 75.5133, -1.4859) -> (62.6116, 75.4153, -1.4859)
  line L3139 (62.6116, 75.4153, -1.4859) -> (62.6116, 74.2153, -1.4859)
  line L3140 (62.6116, 74.2153, -1.4859) -> (62.6068, 74.1173, -1.4859)
  line L3141 (62.6068, 74.1173, -1.4859) -> (62.5685, 73.925, -1.4859)
  line L3142 (62.5685, 73.925, -1.4859) -> (62.4935, 73.7439, -1.4859)
  line L3143 (62.4935, 73.7439, -1.4859) -> (62.3846, 73.5809, -1.4859)
  line L3144 (62.3846, 73.5809, -1.4859) -> (62.246, 73.4423, -1.4859)
  line L3145 (62.246, 73.4423, -1.4859) -> (62.083, 73.3334, -1.4859)
  line L3146 (62.083, 73.3334, -1.4859) -> (61.9019, 73.2583, -1.4859)
  line L3147 (61.9019, 73.2583, -1.4859) -> (61.7096, 73.2201, -1.4859)
  line L3148 (61.7096, 73.2201, -1.4859) -> (61.5136, 73.2201, -1.4859)
  line L3149 (61.5136, 73.2201, -1.4859) -> (61.3213, 73.2583, -1.4859)
  line L3150 (61.3213, 73.2583, -1.4859) -> (61.1402, 73.3334, -1.4859)
  line L3151 (61.1402, 73.3334, -1.4859) -> (60.9772, 73.4423, -1.4859)
  line L3152 (60.9772, 73.4423, -1.4859) -> (60.8386, 73.5809, -1.4859)
  line L3153 (60.8386, 73.5809, -1.4859) -> (60.7297, 73.7439, -1.4859)
  line L3154 (60.7297, 73.7439, -1.4859) -> (60.6547, 73.925, -1.4859)
  line L3155 (60.6547, 73.925, -1.4859) -> (60.6164, 74.1173, -1.4859)
  line L3156 (60.6164, 74.1173, -1.4859) -> (60.6116, 74.2153, -1.4859)
  line L3157 (60.6116, 74.2153, -1.4859) -> (60.6116, 75.4153, -1.4859)
  line L3158 (60.6116, 75.4153, -1.4859) -> (60.6164, 75.5133, -1.4859)
  line L3159 (60.6164, 75.5133, -1.4859) -> (60.6547, 75.7056, -1.4859)
  line L3160 (60.6547, 75.7056, -1.4859) -> (60.7297, 75.8867, -1.4859)
  line L3161 (60.7297, 75.8867, -1.4859) -> (60.8386, 76.0497, -1.4859)
  line L3162 (60.8386, 76.0497, -1.4859) -> (60.9772, 76.1883, -1.4859)
  line L3163 (60.9772, 76.1883, -1.4859) -> (61.1402, 76.2972, -1.4859)
  line L3164 (61.1402, 76.2972, -1.4859) -> (61.3213, 76.3722, -1.4859)
  line L3165 (61.3213, 76.3722, -1.4859) -> (61.5136, 76.4105, -1.4859)
  line L3166 (61.5136, 76.4105, -1.4859) -> (61.7096, 76.4105, -1.4859)
  line L3167 (61.7096, 76.4105, -1.4859) -> (61.9019, 76.3722, -1.4859)
  line L3168 (64.6319, 76.3722, -1.4859) -> (64.813, 76.2972, -1.4859)
  line L3169 (64.813, 76.2972, -1.4859) -> (64.976, 76.1883, -1.4859)
  line L3170 (64.976, 76.1883, -1.4859) -> (65.1146, 76.0497, -1.4859)
  line L3171 (65.1146, 76.0497, -1.4859) -> (65.2235, 75.8867, -1.4859)
  line L3172 (65.2235, 75.8867, -1.4859) -> (65.2985, 75.7056, -1.4859)
  line L3173 (65.2985, 75.7056, -1.4859) -> (65.3368, 75.5133, -1.4859)
  line L3174 (65.3368, 75.5133, -1.4859) -> (65.3416, 75.4153, -1.4859)
  line L3175 (65.3416, 75.4153, -1.4859) -> (65.3416, 74.2153, -1.4859)
  line L3176 (65.3416, 74.2153, -1.4859) -> (65.3368, 74.1173, -1.4859)
  line L3177 (65.3368, 74.1173, -1.4859) -> (65.2985, 73.925, -1.4859)
  line L3178 (65.2985, 73.925, -1.4859) -> (65.2235, 73.7439, -1.4859)
  line L3179 (65.2235, 73.7439, -1.4859) -> (65.1146, 73.5809, -1.4859)
  line L3180 (65.1146, 73.5809, -1.4859) -> (64.976, 73.4423, -1.4859)
  line L3181 (64.976, 73.4423, -1.4859) -> (64.813, 73.3334, -1.4859)
  line L3182 (64.813, 73.3334, -1.4859) -> (64.6319, 73.2583, -1.4859)
  line L3183 (64.6319, 73.2583, -1.4859) -> (64.4396, 73.2201, -1.4859)
  line L3184 (64.4396, 73.2201, -1.4859) -> (64.2436, 73.2201, -1.4859)
  line L3185 (64.2436, 73.2201, -1.4859) -> (64.0513, 73.2583, -1.4859)
  line L3186 (64.0513, 73.2583, -1.4859) -> (63.8702, 73.3334, -1.4859)
  line L3187 (63.8702, 73.3334, -1.4859) -> (63.7072, 73.4423, -1.4859)
  line L3188 (63.7072, 73.4423, -1.4859) -> (63.5686, 73.5809, -1.4859)
  line L3189 (63.5686, 73.5809, -1.4859) -> (63.4597, 73.7439, -1.4859)
  line L3190 (63.4597, 73.7439, -1.4859) -> (63.3847, 73.925, -1.4859)
  line L3191 (63.3847, 73.925, -1.4859) -> (63.3464, 74.1173, -1.4859)
  line L3192 (63.3464, 74.1173, -1.4859) -> (63.3416, 74.2153, -1.4859)
  line L3193 (63.3416, 74.2153, -1.4859) -> (63.3416, 75.4153, -1.4859)
  line L3194 (63.3416, 75.4153, -1.4859) -> (63.3464, 75.5133, -1.4859)
  line L3195 (63.3464, 75.5133, -1.4859) -> (63.3847, 75.7056, -1.4859)
  line L3196 (63.3847, 75.7056, -1.4859) -> (63.4597, 75.8867, -1.4859)
  line L3197 (63.4597, 75.8867, -1.4859) -> (63.5686, 76.0497, -1.4859)
  line L3198 (63.5686, 76.0497, -1.4859) -> (63.7072, 76.1883, -1.4859)
  line L3199 (63.7072, 76.1883, -1.4859) -> (63.8702, 76.2972, -1.4859)
  line L3200 (63.8702, 76.2972, -1.4859) -> (64.0513, 76.3722, -1.4859)
  line L3201 (64.0513, 76.3722, -1.4859) -> (64.2436, 76.4105, -1.4859)
  line L3202 (64.2436, 76.4105, -1.4859) -> (64.4396, 76.4105, -1.4859)
  line L3203 (64.4396, 76.4105, -1.4859) -> (64.6319, 76.3722, -1.4859)
  line L3204 (96.8269, 76.3722, -1.4859) -> (97.008, 76.2972, -1.4859)
  line L3205 (97.008, 76.2972, -1.4859) -> (97.171, 76.1883, -1.4859)
  line L3206 (97.171, 76.1883, -1.4859) -> (97.3096, 76.0497, -1.4859)
  line L3207 (97.3096, 76.0497, -1.4859) -> (97.4185, 75.8867, -1.4859)
  line L3208 (97.4185, 75.8867, -1.4859) -> (97.4935, 75.7056, -1.4859)
  line L3209 (97.4935, 75.7056, -1.4859) -> (97.5318, 75.5133, -1.4859)
  line L3210 (97.5318, 75.5133, -1.4859) -> (97.5366, 75.4153, -1.4859)
  line L3211 (97.5366, 75.4153, -1.4859) -> (97.5366, 74.2153, -1.4859)
  line L3212 (97.5366, 74.2153, -1.4859) -> (97.5318, 74.1173, -1.4859)
  line L3213 (97.5318, 74.1173, -1.4859) -> (97.4935, 73.925, -1.4859)
  line L3214 (97.4935, 73.925, -1.4859) -> (97.4185, 73.7439, -1.4859)
  line L3215 (97.4185, 73.7439, -1.4859) -> (97.3096, 73.5809, -1.4859)
  line L3216 (97.3096, 73.5809, -1.4859) -> (97.171, 73.4423, -1.4859)
  line L3217 (97.171, 73.4423, -1.4859) -> (97.008, 73.3334, -1.4859)
  line L3218 (97.008, 73.3334, -1.4859) -> (96.8269, 73.2583, -1.4859)
  line L3219 (96.8269, 73.2583, -1.4859) -> (96.6346, 73.2201, -1.4859)
  line L3220 (96.6346, 73.2201, -1.4859) -> (96.4386, 73.2201, -1.4859)
  line L3221 (96.4386, 73.2201, -1.4859) -> (96.2463, 73.2583, -1.4859)
  line L3222 (96.2463, 73.2583, -1.4859) -> (96.0652, 73.3334, -1.4859)
  line L3223 (96.0652, 73.3334, -1.4859) -> (95.9022, 73.4423, -1.4859)
  line L3224 (95.9022, 73.4423, -1.4859) -> (95.7636, 73.5809, -1.4859)
  line L3225 (95.7636, 73.5809, -1.4859) -> (95.6547, 73.7439, -1.4859)
  line L3226 (95.6547, 73.7439, -1.4859) -> (95.5797, 73.925, -1.4859)
  line L3227 (95.5797, 73.925, -1.4859) -> (95.5414, 74.1173, -1.4859)
  line L3228 (95.5414, 74.1173, -1.4859) -> (95.5366, 74.2153, -1.4859)
  line L3229 (95.5366, 74.2153, -1.4859) -> (95.5366, 75.4153, -1.4859)
  line L3230 (95.5366, 75.4153, -1.4859) -> (95.5414, 75.5133, -1.4859)
  line L3231 (95.5414, 75.5133, -1.4859) -> (95.5797, 75.7056, -1.4859)
  line L3232 (95.5797, 75.7056, -1.4859) -> (95.6547, 75.8867, -1.4859)
  line L3233 (95.6547, 75.8867, -1.4859) -> (95.7636, 76.0497, -1.4859)
  line L3234 (95.7636, 76.0497, -1.4859) -> (95.9022, 76.1883, -1.4859)
  line L3235 (95.9022, 76.1883, -1.4859) -> (96.0652, 76.2972, -1.4859)
  line L3236 (96.0652, 76.2972, -1.4859) -> (96.2463, 76.3722, -1.4859)
  line L3237 (96.2463, 76.3722, -1.4859) -> (96.4386, 76.4105, -1.4859)
  line L3238 (96.4386, 76.4105, -1.4859) -> (96.6346, 76.4105, -1.4859)
  line L3239 (96.6346, 76.4105, -1.4859) -> (96.8269, 76.3722, -1.4859)
  line L3240 (99.5569, 76.3722, -1.4859) -> (99.738, 76.2972, -1.4859)
  line L3241 (99.738, 76.2972, -1.4859) -> (99.901, 76.1883, -1.4859)
  line L3242 (99.901, 76.1883, -1.4859) -> (100.0396, 76.0497, -1.4859)
  line L3243 (100.0396, 76.0497, -1.4859) -> (100.1485, 75.8867, -1.4859)
  line L3244 (100.1485, 75.8867, -1.4859) -> (100.2235, 75.7056, -1.4859)
  line L3245 (100.2235, 75.7056, -1.4859) -> (100.2618, 75.5133, -1.4859)
  line L3246 (100.2618, 75.5133, -1.4859) -> (100.2666, 75.4153, -1.4859)
  line L3247 (100.2666, 75.4153, -1.4859) -> (100.2666, 74.2153, -1.4859)
  line L3248 (100.2666, 74.2153, -1.4859) -> (100.2618, 74.1173, -1.4859)
  line L3249 (100.2618, 74.1173, -1.4859) -> (100.2235, 73.925, -1.4859)
  line L3250 (100.2235, 73.925, -1.4859) -> (100.1485, 73.7439, -1.4859)
  line L3251 (100.1485, 73.7439, -1.4859) -> (100.0396, 73.5809, -1.4859)
  line L3252 (100.0396, 73.5809, -1.4859) -> (99.901, 73.4423, -1.4859)
  line L3253 (99.901, 73.4423, -1.4859) -> (99.738, 73.3334, -1.4859)
  line L3254 (99.738, 73.3334, -1.4859) -> (99.5569, 73.2583, -1.4859)
  line L3255 (99.5569, 73.2583, -1.4859) -> (99.3646, 73.2201, -1.4859)
  line L3256 (99.3646, 73.2201, -1.4859) -> (99.1686, 73.2201, -1.4859)
  line L3257 (99.1686, 73.2201, -1.4859) -> (98.9763, 73.2583, -1.4859)
  line L3258 (98.9763, 73.2583, -1.4859) -> (98.7952, 73.3334, -1.4859)
  line L3259 (98.7952, 73.3334, -1.4859) -> (98.6322, 73.4423, -1.4859)
  line L3260 (98.6322, 73.4423, -1.4859) -> (98.4936, 73.5809, -1.4859)
  line L3261 (98.4936, 73.5809, -1.4859) -> (98.3847, 73.7439, -1.4859)
  line L3262 (98.3847, 73.7439, -1.4859) -> (98.3097, 73.925, -1.4859)
  line L3263 (98.3097, 73.925, -1.4859) -> (98.2714, 74.1173, -1.4859)
  line L3264 (98.2714, 74.1173, -1.4859) -> (98.2666, 74.2153, -1.4859)
  line L3265 (98.2666, 74.2153, -1.4859) -> (98.2666, 75.4153, -1.4859)
  line L3266 (98.2666, 75.4153, -1.4859) -> (98.2714, 75.5133, -1.4859)
  line L3267 (98.2714, 75.5133, -1.4859) -> (98.3097, 75.7056, -1.4859)
  line L3268 (98.3097, 75.7056, -1.4859) -> (98.3847, 75.8867, -1.4859)
  line L3269 (98.3847, 75.8867, -1.4859) -> (98.4936, 76.0497, -1.4859)
  line L3270 (98.4936, 76.0497, -1.4859) -> (98.6322, 76.1883, -1.4859)
  line L3271 (98.6322, 76.1883, -1.4859) -> (98.7952, 76.2972, -1.4859)
  line L3272 (98.7952, 76.2972, -1.4859) -> (98.9763, 76.3722, -1.4859)
  line L3273 (98.9763, 76.3722, -1.4859) -> (99.1686, 76.4105, -1.4859)
  line L3274 (99.1686, 76.4105, -1.4859) -> (99.3646, 76.4105, -1.4859)
  line L3275 (99.3646, 76.4105, -1.4859) -> (99.5569, 76.3722, -1.4859)
  line L3276 (131.7519, 76.3722, -1.4859) -> (131.933, 76.2972, -1.4859)
  line L3277 (131.933, 76.2972, -1.4859) -> (132.096, 76.1883, -1.4859)
  line L3278 (132.096, 76.1883, -1.4859) -> (132.2346, 76.0497, -1.4859)
  line L3279 (132.2346, 76.0497, -1.4859) -> (132.3435, 75.8867, -1.4859)
  line L3280 (132.3435, 75.8867, -1.4859) -> (132.4185, 75.7056, -1.4859)
  line L3281 (132.4185, 75.7056, -1.4859) -> (132.4568, 75.5133, -1.4859)
  line L3282 (132.4568, 75.5133, -1.4859) -> (132.4616, 75.4153, -1.4859)
  line L3283 (132.4616, 75.4153, -1.4859) -> (132.4616, 74.2153, -1.4859)
  line L3284 (132.4616, 74.2153, -1.4859) -> (132.4568, 74.1173, -1.4859)
  line L3285 (132.4568, 74.1173, -1.4859) -> (132.4185, 73.925, -1.4859)
  line L3286 (132.4185, 73.925, -1.4859) -> (132.3435, 73.7439, -1.4859)
  line L3287 (132.3435, 73.7439, -1.4859) -> (132.2346, 73.5809, -1.4859)
  line L3288 (132.2346, 73.5809, -1.4859) -> (132.096, 73.4423, -1.4859)
  line L3289 (132.096, 73.4423, -1.4859) -> (131.933, 73.3334, -1.4859)
  line L3290 (131.933, 73.3334, -1.4859) -> (131.7519, 73.2583, -1.4859)
  line L3291 (131.7519, 73.2583, -1.4859) -> (131.5596, 73.2201, -1.4859)
  line L3292 (131.5596, 73.2201, -1.4859) -> (131.3636, 73.2201, -1.4859)
  line L3293 (131.3636, 73.2201, -1.4859) -> (131.1713, 73.2583, -1.4859)
  line L3294 (131.1713, 73.2583, -1.4859) -> (130.9902, 73.3334, -1.4859)
  line L3295 (130.9902, 73.3334, -1.4859) -> (130.8272, 73.4423, -1.4859)
  line L3296 (130.8272, 73.4423, -1.4859) -> (130.6886, 73.5809, -1.4859)
  line L3297 (130.6886, 73.5809, -1.4859) -> (130.5797, 73.7439, -1.4859)
  line L3298 (130.5797, 73.7439, -1.4859) -> (130.5047, 73.925, -1.4859)
  line L3299 (130.5047, 73.925, -1.4859) -> (130.4664, 74.1173, -1.4859)
  line L3300 (130.4664, 74.1173, -1.4859) -> (130.4616, 74.2153, -1.4859)
  line L3301 (130.4616, 74.2153, -1.4859) -> (130.4616, 75.4153, -1.4859)
  line L3302 (130.4616, 75.4153, -1.4859) -> (130.4664, 75.5133, -1.4859)
  line L3303 (130.4664, 75.5133, -1.4859) -> (130.5047, 75.7056, -1.4859)
  line L3304 (130.5047, 75.7056, -1.4859) -> (130.5797, 75.8867, -1.4859)
  line L3305 (130.5797, 75.8867, -1.4859) -> (130.6886, 76.0497, -1.4859)
  line L3306 (130.6886, 76.0497, -1.4859) -> (130.8272, 76.1883, -1.4859)
  line L3307 (130.8272, 76.1883, -1.4859) -> (130.9902, 76.2972, -1.4859)
  line L3308 (130.9902, 76.2972, -1.4859) -> (131.1713, 76.3722, -1.4859)
  line L3309 (131.1713, 76.3722, -1.4859) -> (131.3636, 76.4105, -1.4859)
  line L3310 (131.3636, 76.4105, -1.4859) -> (131.5596, 76.4105, -1.4859)
  line L3311 (131.5596, 76.4105, -1.4859) -> (131.7519, 76.3722, -1.4859)
  line L3312 (134.4819, 76.3722, -1.4859) -> (134.663, 76.2972, -1.4859)
  line L3313 (134.663, 76.2972, -1.4859) -> (134.826, 76.1883, -1.4859)
  line L3314 (134.826, 76.1883, -1.4859) -> (134.9646, 76.0497, -1.4859)
  line L3315 (134.9646, 76.0497, -1.4859) -> (135.0735, 75.8867, -1.4859)
  line L3316 (135.0735, 75.8867, -1.4859) -> (135.1485, 75.7056, -1.4859)
  line L3317 (135.1485, 75.7056, -1.4859) -> (135.1868, 75.5133, -1.4859)
  line L3318 (135.1868, 75.5133, -1.4859) -> (135.1916, 75.4153, -1.4859)
  line L3319 (135.1916, 75.4153, -1.4859) -> (135.1916, 74.2153, -1.4859)
  line L3320 (135.1916, 74.2153, -1.4859) -> (135.1868, 74.1173, -1.4859)
  line L3321 (135.1868, 74.1173, -1.4859) -> (135.1485, 73.925, -1.4859)
  line L3322 (135.1485, 73.925, -1.4859) -> (135.0735, 73.7439, -1.4859)
  line L3323 (135.0735, 73.7439, -1.4859) -> (134.9646, 73.5809, -1.4859)
  line L3324 (134.9646, 73.5809, -1.4859) -> (134.826, 73.4423, -1.4859)
  line L3325 (134.826, 73.4423, -1.4859) -> (134.663, 73.3334, -1.4859)
  line L3326 (134.663, 73.3334, -1.4859) -> (134.4819, 73.2583, -1.4859)
  line L3327 (134.4819, 73.2583, -1.4859) -> (134.2896, 73.2201, -1.4859)
  line L3328 (134.2896, 73.2201, -1.4859) -> (134.0936, 73.2201, -1.4859)
  line L3329 (134.0936, 73.2201, -1.4859) -> (133.9013, 73.2583, -1.4859)
  line L3330 (133.9013, 73.2583, -1.4859) -> (133.7202, 73.3334, -1.4859)
  line L3331 (133.7202, 73.3334, -1.4859) -> (133.5572, 73.4423, -1.4859)
  line L3332 (133.5572, 73.4423, -1.4859) -> (133.4186, 73.5809, -1.4859)
  line L3333 (133.4186, 73.5809, -1.4859) -> (133.3097, 73.7439, -1.4859)
  line L3334 (133.3097, 73.7439, -1.4859) -> (133.2347, 73.925, -1.4859)
  line L3335 (133.2347, 73.925, -1.4859) -> (133.1964, 74.1173, -1.4859)
  line L3336 (133.1964, 74.1173, -1.4859) -> (133.1916, 74.2153, -1.4859)
  line L3337 (133.1916, 74.2153, -1.4859) -> (133.1916, 75.4153, -1.4859)
  line L3338 (133.1916, 75.4153, -1.4859) -> (133.1964, 75.5133, -1.4859)
  line L3339 (133.1964, 75.5133, -1.4859) -> (133.2347, 75.7056, -1.4859)
  line L3340 (133.2347, 75.7056, -1.4859) -> (133.3097, 75.8867, -1.4859)
  line L3341 (133.3097, 75.8867, -1.4859) -> (133.4186, 76.0497, -1.4859)
  line L3342 (133.4186, 76.0497, -1.4859) -> (133.5572, 76.1883, -1.4859)
  line L3343 (133.5572, 76.1883, -1.4859) -> (133.7202, 76.2972, -1.4859)
  line L3344 (133.7202, 76.2972, -1.4859) -> (133.9013, 76.3722, -1.4859)
  line L3345 (133.9013, 76.3722, -1.4859) -> (134.0936, 76.4105, -1.4859)
  line L3346 (134.0936, 76.4105, -1.4859) -> (134.2896, 76.4105, -1.4859)
  line L3347 (134.2896, 76.4105, -1.4859) -> (134.4819, 76.3722, -1.4859)
  line L3348 (14.3815, 73.2735, -1.4859) -> (12.3815, 73.2735, -1.4859)
  line L3349 (12.3815, 73.2735, -1.4859) -> (12.3815, 76.4735, -1.4859)
  line L3350 (12.3815, 76.4735, -1.4859) -> (14.3815, 76.4735, -1.4859)
  line L3351 (14.3815, 76.4735, -1.4859) -> (14.3815, 73.2735, -1.4859)
  line L3352 (49.3065, 73.2735, -1.4859) -> (47.3065, 73.2735, -1.4859)